Autodesk Fusion 360 part; units mm, degrees
(part 2 of 3)
sketch "Sketch3" plane through (0, -4, 0) normal (0, -1, 0) x (1, 0, 0)
  line L0 (-7.05, 59.625) -> (-3.6735, 85.6389)
  line L1 (-3.6735, 85.6389) -> (56.3105, 101.7115)
  line L2 (56.3105, 101.7115) -> (67.4527, 60.1284)
  line L3 (67.4527, 60.1284) -> (69.15, 48.195)
  line L4 (69.15, 48.195) -> (69.15, -71.055)
  line L5 (69.15, -71.055) -> (31.05, -71.055)
  line L6 (31.05, -71.055) -> (31.05, -76.77)
  line L7 (31.05, -76.77) -> (7.05, -76.77)
  line L8 (7.05, -76.77) -> (7.05, -69.15)
  line L9 (7.05, -69.15) -> (-12, -69.15)
  line L10 (-12, -69.15) -> (-12, -59.625)
  line L11 (-12, -59.625) -> (-69.15, -59.625)
  line L12 (-69.15, -59.625) -> (-69.15, 59.625)
  line L13 (-69.15, 59.625) -> (-7.05, 59.625)
  line L14 (-12.7285, 93.5653) -> (-15.8359, 69.625)
  line L15 (-15.8359, 69.625) -> (-79.15, 69.625)
  line L16 (-79.15, 69.625) -> (-79.15, -69.625)
  line L17 (-79.15, -69.625) -> (-22, -69.625)
  line L18 (-22, -69.625) -> (-22, -79.15)
  line L19 (-22, -79.15) -> (-2.95, -79.15)
  line L20 (-2.95, -79.15) -> (-2.95, -86.77)
  line L21 (-2.95, -86.77) -> (41.05, -86.77)
  line L22 (41.05, -86.77) -> (41.05, -81.055)
  line L23 (41.05, -81.055) -> (79.15, -81.055)
  line L24 (79.15, -81.055) -> (79.15, 48.9026)
  line L25 (79.15, 48.9026) -> (77.2681, 62.1339)
  line L26 (77.2681, 62.1339) -> (63.3816, 113.959)
  line L27 (63.3816, 113.959) -> (-12.7285, 93.5653)
  line L28 (69.15, -71.055) -> (59.15, -71.055)
  line L29 (59.15, -71.055) -> (59.15, -81.055)
  line L30 (69.15, -71.055) -> (69.15, -61.055)
  line L31 (69.15, -61.055) -> (79.15, -61.055)
  line L32 (-69.15, -59.625) -> (-59.15, -59.625)
  line L33 (-59.15, -59.625) -> (-59.15, -69.625)
  line L34 (-69.15, -59.625) -> (-69.15, -49.625)
  line L35 (-69.15, -49.625) -> (-79.15, -49.625)
  line L36 (-69.15, 59.625) -> (-59.15, 59.625)
  line L37 (-59.15, 59.625) -> (-59.15, 69.625)
  line L38 (-69.15, 59.625) -> (-69.15, 49.625)
  line L39 (-69.15, 49.625) -> (-79.15, 49.625)
  line L40 (56.3105, 101.7115) -> (58.8987, 92.0523)
  line L41 (58.8987, 92.0523) -> (68.558, 94.6405)
  line L42 (56.3105, 101.7115) -> (46.6513, 99.1233)
  line L43 (46.6513, 99.1233) -> (44.0631, 108.7826)
  line L44 (56.3105, 101.7115) -> (63.3816, 113.959) construction
  circle A0 centre (63.3816, 113.959) radius 8.75 construction
  circle A1 centre (59.0066, 106.3813) radius 1.75
  line L45 (-69.15, 59.625) -> (-79.15, 69.625) construction
  circle A2 centre (-79.15, 69.625) radius 8.75 construction
  line L46 (-69.15, -59.625) -> (-79.15, -69.625) construction
  circle A3 centre (-79.15, -69.625) radius 8.75 construction
  line L47 (69.15, -71.055) -> (79.15, -81.055) construction
  circle A4 centre (79.15, -81.055) radius 8.75 construction
  circle A5 centre (-72.9628, 63.4378) radius 1.75
  circle A6 centre (-72.9628, -63.4378) radius 1.75
  circle A7 centre (72.9628, -74.8678) radius 1.75
  line L48 (-3.6735, 85.6389) -> (-12.7285, 93.5653) construction
  line L49 (19.05, -86.77) -> (19.05, -74.6491) construction
  line L50 (-12, -59.625) -> (-59.15, -59.625) construction
  line L51 (-35.575, -59.625) -> (-35.575, -69.625) construction
  line L52 (69.15, 48.195) -> (79.15, 48.195) construction
  line L53 (74.15, -61.055) -> (74.15, 48.195) construction
  line L54 (-74.15, -49.625) -> (-74.15, 49.625) construction
  line L55 (-74.15, -49.625) -> (-116.3664, 10.6447) construction
  circle A8 centre (-116.3664, 10.6447) radius 73.5844 construction
  circle A9 centre (-158.5827, 70.9145) radius 73.5844 construction
  line L56 (-116.3664, 10.6447) -> (-188.0343, 112.9607) construction
  line L57 (-200.7991, 131.1842) -> (-74.15, 49.625) construction
  circle A10 centre (-200.7991, 131.1842) radius 73.5844 construction
  line L58 (-158.5827, 70.9145) -> (-138.933, 91.3438) construction
  circle A11 centre (-116.3664, 10.6447) radius 28.3455 construction
  line L59 (-116.3664, 10.6447) -> (-144.4165, 6.563) construction
  line L60 (-158.5827, 70.9145) -> (-96.7167, 31.0741) construction
  line L61 (-96.7167, 31.0741) -> (-29.6505, -12.115) construction
  circle A12 centre (-74.15, -49.625) radius 28.3455 construction
  line L62 (-74.15, -49.625) -> (-99.7632, -37.4829) construction
  line L63 (-116.3664, 10.6447) -> (-54.5003, -29.1956) construction
  circle A13 centre (-74.15, 16.5417) radius 1.25
  circle A14 centre (-74.15, -16.5417) radius 1.25
  circle A15 centre (19.05, -80.7095) radius 1.25
  circle A16 centre (-35.575, -64.625) radius 1.25
  line L64 (-7.05, 59.625) -> (-15.8359, 69.625) construction
  line L65 (-59.15, 64.625) -> (-11.443, 64.625) construction
  circle A17 centre (-35.2965, 64.625) radius 1.25
  line L66 (-5.3617, 72.6319) -> (-14.2822, 81.5952) construction
  line L67 (26.3185, 93.6752) -> (23.7303, 103.3345) construction
  line L68 (25.0244, 98.5048) -> (-9.822, 77.1136) construction
  line L69 (7.6012, 87.8092) -> (-12.7285, 93.5653) construction
  line L70 (-2.5637, 90.6873) -> (-8.201, 89.6021) construction
  line L71 (-2.5637, 90.6873) -> (-6.6059, 88.2058) construction
  line L72 (-6.6059, 88.2058) -> (-8.201, 89.6021) construction
  circle A18 centre (-7.4035, 88.904) radius 1.25
  line L73 (74.15, -61.055) -> (120.3943, 61.6463) construction
  circle A19 centre (74.15, -61.055) radius 30 construction
  circle A20 centre (84.7301, -32.9826) radius 30 construction
  circle A21 centre (95.3102, -4.9101) radius 30 construction
  circle A22 centre (105.8902, 23.1623) radius 30 construction
  line L74 (105.8902, 23.1623) -> (74.15, 48.195) construction
  line L75 (95.3102, -4.9101) -> (82.3346, 41.74) construction
  circle A23 centre (84.7301, -32.9826) radius 48.4211 construction
  circle A24 centre (74.15, -61.055) radius 48.4211 construction
  line L76 (74.15, -61.055) -> (120.8632, -73.8016) construction
  line L77 (84.7301, -32.9826) -> (131.4433, -45.7292) construction
  line L78 (95.3102, -4.9101) -> (71.7545, 13.6676) construction
  line L79 (84.7301, -32.9826) -> (61.1744, -14.4048) construction
  circle A25 centre (74.15, 11.7783) radius 1.25
  circle A26 centre (74.15, -24.6383) radius 1.25
  line L80 (67.4527, 60.1284) -> (77.1119, 62.7166) construction
  line L81 (72.2823, 61.4225) -> (63.7283, 93.3464) construction
  line L82 (72.2823, 61.4225) -> (80.0066, 107.5296) construction
  circle A27 centre (72.2823, 61.4225) radius 10 construction
  circle A28 centre (73.9346, 71.2851) radius 10 construction
  circle A29 centre (75.5869, 81.1476) radius 10 construction
  circle A30 centre (77.2391, 91.0102) radius 10 construction
  line L83 (77.2391, 91.0102) -> (63.7283, 93.3464) construction
  line L84 (75.5869, 81.1476) -> (67.3854, 92.714) construction
  circle A31 centre (72.2823, 61.4225) radius 14.1791 construction
  line L85 (72.2823, 61.4225) -> (86.4251, 60.4088) construction
  line L86 (64.0808, 72.9889) -> (73.9346, 71.2851) construction
  circle A32 centre (69.431, 72.0638) radius 1.25
  point P0 (-74.15, -16.5417)
  point P1 (-74.15, 16.5417)
  dimension "d195" = 10
  dimension "d196" = 10
  dimension "d197" = 10
  dimension "d198" = 10
  dimension "d199" = 10
  dimension "d200" = 10
  dimension "d201" = 10
  dimension "d202" = 10
  dimension "d203" = 17.5
  dimension "d204" = 3.5
  dimension "d205" = 17.5
  dimension "d206" = 17.5
  dimension "d207" = 17.5
  dimension "d208" = 3.5
  dimension "d209" = 3.5
  dimension "d210" = 3.5
  dimension "d216" = 2.5
  dimension "d217" = 2.5
  dimension "d218" = 2.5
  dimension "d219" = 2.5
  dimension "d224" = 2.5
  dimension "d250" = 2.5
  dimension "d251" = 60
  dimension "d252" = 60
  dimension "d253" = 60
  dimension "d254" = 2.5
  dimension "d255" = 2.5
  dimension "d261" = 20
  dimension "d262" = 2.5
  constraint coincident L4.end L5.start
  constraint perpendicular L4 L28
  constraint coincident L23 L29.end
  constraint perpendicular L23 L29
  constraint perpendicular L5 L30
  constraint coincident L24 L31.end
  constraint perpendicular L24 L31
  constraint coincident L11.end L12.start
  constraint perpendicular L12 L32
  constraint coincident L17 L33.end
  constraint perpendicular L17 L33
  constraint perpendicular L11 L34
  constraint coincident L16 L35.end
  constraint perpendicular L16 L35
  constraint coincident L12.end L13.start
  constraint perpendicular L12 L36
  constraint coincident L15 L37.end
  constraint perpendicular L15 L37
  constraint perpendicular L13 L38
  constraint coincident L16 L39.end
  constraint perpendicular L16 L39
  constraint coincident L1.end L2.start
  constraint perpendicular L1 L40
  constraint coincident L26 L41.end
  constraint perpendicular L26 L41
  constraint perpendicular L2 L42
  constraint coincident L27 L43.end
  constraint perpendicular L27 L43
  constraint coincident L26.end L27.start
  constraint coincident A0 A1.centre
  constraint coincident L44 A1.centre
  constraint coincident L15.end L16.start
  constraint coincident L16.end L17.start
  constraint coincident L23.end L24.start
  constraint coincident A2 A5.centre
  constraint coincident L45 A5.centre
  constraint coincident A3 A6.centre
  constraint coincident L46 A6.centre
  constraint coincident A4 A7.centre
  constraint coincident L47 A7.centre
  constraint coincident L0.end L1.start
  constraint coincident L14.start L27.end
  constraint midpoint L21 L49.start
  constraint perpendicular L21 L49
  constraint coincident L10.end L11.start
  constraint midpoint L50 L51.start
  constraint coincident L17 L51.end
  constraint perpendicular L17 L51
  constraint coincident L3.end L4.start
  constraint coincident L24 L52.end
  constraint perpendicular L24 L52
  constraint midpoint L31 L53.start
  constraint midpoint L52 L53.end
  constraint midpoint L35 L54.start
  constraint midpoint L39 L54.end
  constraint coincident L55.end A8.centre
  constraint coincident L54.start A8
  constraint coincident A8 A9.centre
  constraint coincident L55.end A9
  constraint coincident A9 L57.start
  constraint coincident L56 L57.start
  constraint coincident L57.start A10.centre
  constraint coincident A9.centre A10
  constraint coincident A9.centre L58.start
  constraint coincident A10 L58.end
  constraint coincident L57 L58.end
  constraint coincident A11 L59.end
  constraint collinear L55 L56
  constraint collinear A9.centre L56.end L55.end
  constraint collinear L54.start L57.start L55.end
  constraint concentric A8 A11
  constraint equal L58 L59
  constraint coincident A9 L60.end
  constraint coincident A11 L60.end
  constraint collinear L60 L61
  constraint coincident L54.start L55.start
  constraint coincident A12 L62.end
  constraint equal L58 L62
  constraint coincident A12 L63.end
  constraint coincident A8 L63.end
  constraint coincident L63 P0
  constraint coincident L54 P0
  constraint coincident L61 P1
  constraint coincident L54 P1
  constraint coincident P1 A13.centre
  constraint coincident P0 A14.centre
  constraint midpoint L49 A15.centre
  constraint midpoint L51 A16.centre
  constraint coincident L0.start L13.end
  constraint coincident L14.end L15.start
  constraint midpoint L37 L65.start
  constraint midpoint L64 L65.end
  constraint midpoint L65 A17.centre
  constraint midpoint L0 L66.start
  constraint midpoint L14 L66.end
  constraint midpoint L1 L67.start
  constraint coincident L27 L67.end
  constraint perpendicular L27 L67
  constraint midpoint L67 L68.start
  constraint midpoint L66 L68.end
  constraint midpoint L68 L69.start
  constraint midpoint L69 L70.start
  constraint midpoint L48 L70.end
  constraint coincident L48 L71.end
  constraint parallel L68 L71
  constraint midpoint L72 A18.centre
  constraint coincident L53.start L73.start
  constraint coincident A19 A20.centre
  constraint coincident L73 A20.centre
  constraint coincident A20 A21.centre
  constraint coincident L73 A21.centre
  constraint coincident A21 A22.centre
  constraint coincident L73 A22.centre
  constraint coincident A21.centre A22
  constraint coincident A22.centre L74.start
  constraint coincident A21.centre L75.start
  constraint coincident A22 L75.end
  constraint coincident L74 L75.end
  constraint concentric A20 A23
  constraint coincident A24 L76.end
  constraint coincident A20.centre A23.centre
  constraint coincident A23 L77.end
  constraint parallel L76 L77
  constraint equal L75 L77
  constraint equal L75 L76
  constraint coincident A23 L78.end
  constraint coincident A21 L78.end
  constraint coincident A20 L79.end
  constraint coincident A24 L79.end
  constraint coincident L78 A25.centre
  constraint coincident L53 A25.centre
  constraint coincident L79 A26.centre
  constraint coincident L53 A26.centre
  constraint coincident L2.end L3.start
  constraint coincident L26 L80.end
  constraint perpendicular L26 L80
  constraint midpoint L80 L81.start
  constraint midpoint L41 L81.end
  constraint coincident L81.start L82.start
  constraint coincident A27 A28.centre
  constraint coincident L82 A28.centre
  constraint coincident L81.start A28
  constraint coincident A28 A29.centre
  constraint coincident L82 A29.centre
  constraint coincident A28.centre A29
  constraint coincident L82 A30.centre
  constraint coincident A29 A30.centre
  constraint coincident A29.centre A30
  constraint coincident A30.centre L83.start
  constraint coincident A29.centre L84.start
  constraint coincident A30 L84.end
  constraint coincident L83 L84.end
  constraint coincident A31 L85.end
  constraint equal L84 L85
  constraint coincident A28 L86.start
  constraint coincident A31 L86.start
  constraint coincident A28.centre L86.end
  constraint coincident L81 A32.centre
  constraint coincident L86 A32.centre
  measures "d195" distance of L4.end L28.end
  measures "d196" distance of L4.end L30.end
  measures "d197" distance of L11.end L32.end
  measures "d198" distance of L11.end L34.end
  measures "d199" distance of L12.end L36.end
  measures "d200" distance of L12.end L38.end
  measures "d201" distance of L1.end L40.end
  measures "d202" distance of L1.end L42.end
  measures "d203" diameter of A0
  measures "d204" diameter of A1
  measures "d205" diameter of A2
  measures "d206" diameter of A3
  measures "d207" diameter of A4
  measures "d208" diameter of A5
  measures "d209" diameter of A6
  measures "d210" diameter of A7
  measures "d216" diameter of A13
  measures "d217" diameter of A14
  measures "d218" diameter of A15
  measures "d219" diameter of A16
  measures "d224" diameter of A17
  measures "d250" diameter of A18
  measures "d251" diameter of A19
  measures "d252" diameter of A20
  measures "d253" diameter of A21
  measures "d254" diameter of A25
  measures "d255" diameter of A26
  measures "d261" diameter of A27
  measures "d262" diameter of A32
extrude "Extrude5" add sketch "Sketch3" along normal blind 3.2 contours L12 L13 L15 L16 L36 L37 L38 L39 | L1 L2 L26 L27 L40 L41 L42 L43 | L11 L12 L16 L17 L32 L33 L34 L35 | L4 L5 L23 L24 L28 L29 L30 L31
extrude "Extrude4" add sketch "Sketch3" along normal blind 0.7 contours A1 | A5 | A6 | A7
extrude "Extrude6" add sketch "Sketch3" along normal blind 5 contours A13 | A14 | A15 | A16 | A17 | A18 | A25 | A26 | A32
fillet "Fillet2" radius 1.25 9 edges at (-36.4619, -9, 64.173) (17.8846, -9, -81.1616) (-36.7404, -9, -65.077) (-75.3154, -9, -16.9937) (-75.3154, -9, 16.0896) (-8.5689, -9, 88.4519) (72.9846, -9, 11.3263) (72.9846, -9, -25.0904) (68.2656, -9, 71.6118)
extrude "Extrude7" add sketch "Sketch1" along normal blind 2.5
sketch "Sketch4" plane through (0, 0, 0) normal (0, 1, 0) x (-1, 0, 0)
  line L0 (3.6735, 85.6389) -> (-56.3105, 101.7115)
  line L1 (-56.3105, 101.7115) -> (-67.4527, 60.1284)
  line L2 (-67.4527, 60.1284) -> (-69.15, 48.195)
  line L3 (-69.15, 48.195) -> (-69.15, -71.055)
  line L4 (-69.15, -71.055) -> (-31.05, -71.055)
  line L5 (-31.05, -71.055) -> (-31.05, -76.77)
  line L6 (-31.05, -76.77) -> (-7.05, -76.77)
  line L7 (-7.05, -76.77) -> (-7.05, -69.15)
  line L8 (-7.05, -69.15) -> (12, -69.15)
  line L9 (12, -69.15) -> (12, -59.625)
  line L10 (12, -59.625) -> (69.15, -59.625)
  line L11 (69.15, -59.625) -> (69.15, 59.625)
  line L12 (69.15, 59.625) -> (7.05, 59.625)
  line L13 (7.05, 59.625) -> (3.6735, 85.6389)
  line L14 (-21.0175, 72.1887) -> (-17.2125, 86.4394)
  arc A0 (-15.9884, 87.1476) -> (-17.2125, 86.4394) centre (-16.2463, 86.1815) ccw
  line L15 (-15.9884, 87.1476) -> (-1.7376, 83.3426)
  arc A1 (-1.0294, 82.1185) -> (-1.7376, 83.3426) centre (-1.9956, 82.3765) ccw
  line L16 (-1.0294, 82.1185) -> (-4.8344, 67.8677)
  arc A2 (-6.0585, 67.1595) -> (-4.8344, 67.8677) centre (-5.8006, 68.1257) ccw
  line L17 (-6.0585, 67.1595) -> (-20.3093, 70.9646)
  arc A3 (-21.0175, 72.1887) -> (-20.3093, 70.9646) centre (-20.0513, 71.9307) ccw
  line L18 (-44.3489, 58.7183) -> (-40.5439, 72.9691)
  arc A4 (-39.3198, 73.6772) -> (-40.5439, 72.9691) centre (-39.5777, 72.7111) ccw
  line L19 (-39.3198, 73.6772) -> (-25.069, 69.8722)
  arc A5 (-24.3608, 68.6481) -> (-25.069, 69.8722) centre (-25.327, 68.9061) ccw
  line L20 (-24.3608, 68.6481) -> (-28.1658, 54.3974)
  arc A6 (-29.3899, 53.6892) -> (-28.1658, 54.3974) centre (-29.132, 54.6553) ccw
  line L21 (-29.3899, 53.6892) -> (-43.6407, 57.4942)
  arc A7 (-44.3489, 58.7183) -> (-43.6407, 57.4942) centre (-43.3827, 58.4603) ccw
  line L22 (-46.475, 9.77) -> (-46.475, 24.52)
  arc A8 (-45.475, 25.52) -> (-46.475, 24.52) centre (-45.475, 24.52) ccw
  line L23 (-45.475, 25.52) -> (-30.725, 25.52)
  arc A9 (-29.725, 24.52) -> (-30.725, 25.52) centre (-30.725, 24.52) ccw
  line L24 (-29.725, 24.52) -> (-29.725, 9.77)
  arc A10 (-30.725, 8.77) -> (-29.725, 9.77) centre (-30.725, 9.77) ccw
  line L25 (-30.725, 8.77) -> (-45.475, 8.77)
  arc A11 (-46.475, 9.77) -> (-45.475, 8.77) centre (-45.475, 9.77) ccw
  line L26 (-46.475, -9.28) -> (-46.475, 5.47)
  arc A12 (-45.475, 6.47) -> (-46.475, 5.47) centre (-45.475, 5.47) ccw
  line L27 (-45.475, 6.47) -> (-30.725, 6.47)
  arc A13 (-29.725, 5.47) -> (-30.725, 6.47) centre (-30.725, 5.47) ccw
  line L28 (-29.725, 5.47) -> (-29.725, -9.28)
  arc A14 (-30.725, -10.28) -> (-29.725, -9.28) centre (-30.725, -9.28) ccw
  line L29 (-30.725, -10.28) -> (-45.475, -10.28)
  arc A15 (-46.475, -9.28) -> (-45.475, -10.28) centre (-45.475, -9.28) ccw
  line L30 (-8.375, -26.425) -> (-8.375, -11.675)
  arc A16 (-7.375, -10.675) -> (-8.375, -11.675) centre (-7.375, -11.675) ccw
  line L31 (-7.375, -10.675) -> (7.375, -10.675)
  arc A17 (8.375, -11.675) -> (7.375, -10.675) centre (7.375, -11.675) ccw
  line L32 (8.375, -11.675) -> (8.375, -26.425)
  arc A18 (7.375, -27.425) -> (8.375, -26.425) centre (7.375, -26.425) ccw
  line L33 (7.375, -27.425) -> (-7.375, -27.425)
  arc A19 (-8.375, -26.425) -> (-7.375, -27.425) centre (-7.375, -26.425) ccw
  line L34 (-8.375, 30.725) -> (-8.375, 45.475)
  arc A20 (-7.375, 46.475) -> (-8.375, 45.475) centre (-7.375, 45.475) ccw
  line L35 (-7.375, 46.475) -> (7.375, 46.475)
  arc A21 (8.375, 45.475) -> (7.375, 46.475) centre (7.375, 45.475) ccw
  line L36 (8.375, 45.475) -> (8.375, 30.725)
  arc A22 (7.375, 29.725) -> (8.375, 30.725) centre (7.375, 30.725) ccw
  line L37 (7.375, 29.725) -> (-7.375, 29.725)
  arc A23 (-8.375, 30.725) -> (-7.375, 29.725) centre (-7.375, 30.725) ccw
  line L38 (11.675, 17.9) -> (26.425, 17.9)
  arc A24 (27.425, 16.9) -> (26.425, 17.9) centre (26.425, 16.9) ccw
  line L39 (27.425, 16.9) -> (27.425, 2.15)
  arc A25 (26.425, 1.15) -> (27.425, 2.15) centre (26.425, 2.15) ccw
  line L40 (26.425, 1.15) -> (11.675, 1.15)
  arc A26 (10.675, 2.15) -> (11.675, 1.15) centre (11.675, 2.15) ccw
  line L41 (10.675, 2.15) -> (10.675, 16.9)
  arc A27 (11.675, 17.9) -> (10.675, 16.9) centre (11.675, 16.9) ccw
  line L42 (30.725, -1.15) -> (64.525, -1.15)
  arc A28 (65.525, -2.15) -> (64.525, -1.15) centre (64.525, -2.15) ccw
  line L43 (65.525, -2.15) -> (65.525, -16.9)
  arc A29 (64.525, -17.9) -> (65.525, -16.9) centre (64.525, -16.9) ccw
  line L44 (64.525, -17.9) -> (30.725, -17.9)
  arc A30 (29.725, -16.9) -> (30.725, -17.9) centre (30.725, -16.9) ccw
  line L45 (29.725, -16.9) -> (29.725, -2.15)
  arc A31 (30.725, -1.15) -> (29.725, -2.15) centre (30.725, -2.15) ccw
  line L46 (-8.375, -45.475) -> (-8.375, -30.725)
  arc A32 (-7.375, -29.725) -> (-8.375, -30.725) centre (-7.375, -30.725) ccw
  line L47 (-7.375, -29.725) -> (7.375, -29.725)
  arc A33 (8.375, -30.725) -> (7.375, -29.725) centre (7.375, -30.725) ccw
  line L48 (8.375, -30.725) -> (8.375, -45.475)
  arc A34 (7.375, -46.475) -> (8.375, -45.475) centre (7.375, -45.475) ccw
  line L49 (7.375, -46.475) -> (-7.375, -46.475)
  arc A35 (-8.375, -45.475) -> (-7.375, -46.475) centre (-7.375, -45.475) ccw
  line L50 (-65.525, -66.43) -> (-65.525, -51.68)
  arc A36 (-64.525, -50.68) -> (-65.525, -51.68) centre (-64.525, -51.68) ccw
  line L51 (-64.525, -50.68) -> (-49.775, -50.68)
  arc A37 (-48.775, -51.68) -> (-49.775, -50.68) centre (-49.775, -51.68) ccw
  line L52 (-48.775, -51.68) -> (-48.775, -66.43)
  arc A38 (-49.775, -67.43) -> (-48.775, -66.43) centre (-49.775, -66.43) ccw
  line L53 (-49.775, -67.43) -> (-64.525, -67.43)
  arc A39 (-65.525, -66.43) -> (-64.525, -67.43) centre (-64.525, -66.43) ccw
  line L54 (11.675, -39.25) -> (26.425, -39.25)
  arc A40 (27.425, -40.25) -> (26.425, -39.25) centre (26.425, -40.25) ccw
  line L55 (27.425, -40.25) -> (27.425, -55)
  arc A41 (26.425, -56) -> (27.425, -55) centre (26.425, -55) ccw
  line L56 (26.425, -56) -> (11.675, -56)
  arc A42 (10.675, -55) -> (11.675, -56) centre (11.675, -55) ccw
  line L57 (10.675, -55) -> (10.675, -40.25)
  arc A43 (11.675, -39.25) -> (10.675, -40.25) centre (11.675, -40.25) ccw
  line L58 (-7.375, -48.775) -> (7.375, -48.775)
  arc A44 (8.375, -49.775) -> (7.375, -48.775) centre (7.375, -49.775) ccw
  line L59 (8.375, -49.775) -> (8.375, -64.525)
  arc A45 (7.375, -65.525) -> (8.375, -64.525) centre (7.375, -64.525) ccw
  line L60 (7.375, -65.525) -> (-7.375, -65.525)
  arc A46 (-8.375, -64.525) -> (-7.375, -65.525) centre (-7.375, -64.525) ccw
  line L61 (-8.375, -64.525) -> (-8.375, -49.775)
  arc A47 (-7.375, -48.775) -> (-8.375, -49.775) centre (-7.375, -49.775) ccw
  line L62 (-65.525, -47.38) -> (-65.525, -32.63)
  arc A48 (-64.525, -31.63) -> (-65.525, -32.63) centre (-64.525, -32.63) ccw
  line L63 (-64.525, -31.63) -> (-49.775, -31.63)
  arc A49 (-48.775, -32.63) -> (-49.775, -31.63) centre (-49.775, -32.63) ccw
  line L64 (-48.775, -32.63) -> (-48.775, -47.38)
  arc A50 (-49.775, -48.38) -> (-48.775, -47.38) centre (-49.775, -47.38) ccw
  line L65 (-49.775, -48.38) -> (-64.525, -48.38)
  arc A51 (-65.525, -47.38) -> (-64.525, -48.38) centre (-64.525, -47.38) ccw
  line L66 (11.675, -20.2) -> (26.425, -20.2)
  arc A52 (27.425, -21.2) -> (26.425, -20.2) centre (26.425, -21.2) ccw
  line L67 (27.425, -21.2) -> (27.425, -35.95)
  arc A53 (26.425, -36.95) -> (27.425, -35.95) centre (26.425, -35.95) ccw
  line L68 (26.425, -36.95) -> (11.675, -36.95)
  arc A54 (10.675, -35.95) -> (11.675, -36.95) centre (11.675, -35.95) ccw
  line L69 (10.675, -35.95) -> (10.675, -21.2)
  arc A55 (11.675, -20.2) -> (10.675, -21.2) centre (11.675, -21.2) ccw
  line L70 (30.725, 17.9) -> (64.525, 17.9)
  arc A56 (65.525, 16.9) -> (64.525, 17.9) centre (64.525, 16.9) ccw
  line L71 (65.525, 16.9) -> (65.525, 2.15)
  arc A57 (64.525, 1.15) -> (65.525, 2.15) centre (64.525, 2.15) ccw
  line L72 (64.525, 1.15) -> (30.725, 1.15)
  arc A58 (29.725, 2.15) -> (30.725, 1.15) centre (30.725, 2.15) ccw
  line L73 (29.725, 2.15) -> (29.725, 16.9)
  arc A59 (30.725, 17.9) -> (29.725, 16.9) centre (30.725, 16.9) ccw
  line L74 (11.675, -1.15) -> (26.425, -1.15)
  arc A60 (27.425, -2.15) -> (26.425, -1.15) centre (26.425, -2.15) ccw
  line L75 (27.425, -2.15) -> (27.425, -16.9)
  arc A61 (26.425, -17.9) -> (27.425, -16.9) centre (26.425, -16.9) ccw
  line L76 (26.425, -17.9) -> (11.675, -17.9)
  arc A62 (10.675, -16.9) -> (11.675, -17.9) centre (11.675, -16.9) ccw
  line L77 (10.675, -16.9) -> (10.675, -2.15)
  arc A63 (11.675, -1.15) -> (10.675, -2.15) centre (11.675, -2.15) ccw
  line L78 (10.675, 40.25) -> (10.675, 55)
  arc A64 (11.675, 56) -> (10.675, 55) centre (11.675, 55) ccw
  line L79 (11.675, 56) -> (26.425, 56)
  arc A65 (27.425, 55) -> (26.425, 56) centre (26.425, 55) ccw
  line L80 (27.425, 55) -> (27.425, 40.25)
  arc A66 (26.425, 39.25) -> (27.425, 40.25) centre (26.425, 40.25) ccw
  line L81 (26.425, 39.25) -> (11.675, 39.25)
  arc A67 (10.675, 40.25) -> (11.675, 39.25) centre (11.675, 40.25) ccw
  line L82 (-27.425, -34.045) -> (-27.425, -19.295)
  arc A68 (-26.425, -18.295) -> (-27.425, -19.295) centre (-26.425, -19.295) ccw
  line L83 (-26.425, -18.295) -> (-11.675, -18.295)
  arc A69 (-10.675, -19.295) -> (-11.675, -18.295) centre (-11.675, -19.295) ccw
  line L84 (-10.675, -19.295) -> (-10.675, -34.045)
  arc A70 (-11.675, -35.045) -> (-10.675, -34.045) centre (-11.675, -34.045) ccw
  line L85 (-11.675, -35.045) -> (-26.425, -35.045)
  arc A71 (-27.425, -34.045) -> (-26.425, -35.045) centre (-26.425, -34.045) ccw
  line L86 (-65.525, -28.33) -> (-65.525, -13.58)
  arc A72 (-64.525, -12.58) -> (-65.525, -13.58) centre (-64.525, -13.58) ccw
  line L87 (-64.525, -12.58) -> (-49.775, -12.58)
  arc A73 (-48.775, -13.58) -> (-49.775, -12.58) centre (-49.775, -13.58) ccw
  line L88 (-48.775, -13.58) -> (-48.775, -28.33)
  arc A74 (-49.775, -29.33) -> (-48.775, -28.33) centre (-49.775, -28.33) ccw
  line L89 (-49.775, -29.33) -> (-64.525, -29.33)
  arc A75 (-65.525, -28.33) -> (-64.525, -29.33) centre (-64.525, -28.33) ccw
  line L90 (-27.425, 4.055) -> (-27.425, 18.805)
  arc A76 (-26.425, 19.805) -> (-27.425, 18.805) centre (-26.425, 18.805) ccw
  line L91 (-26.425, 19.805) -> (-11.675, 19.805)
  arc A77 (-10.675, 18.805) -> (-11.675, 19.805) centre (-11.675, 18.805) ccw
  line L92 (-10.675, 18.805) -> (-10.675, 4.055)
  arc A78 (-11.675, 3.055) -> (-10.675, 4.055) centre (-11.675, 4.055) ccw
  line L93 (-11.675, 3.055) -> (-26.425, 3.055)
  arc A79 (-27.425, 4.055) -> (-26.425, 3.055) centre (-26.425, 4.055) ccw
  line L94 (-62.7498, 63.6488) -> (-58.9448, 77.8996)
  arc A80 (-57.7207, 78.6078) -> (-58.9448, 77.8996) centre (-57.9786, 77.6416) ccw
  line L95 (-57.7207, 78.6078) -> (-43.4699, 74.8027)
  arc A81 (-42.7617, 73.5786) -> (-43.4699, 74.8027) centre (-43.7278, 73.8366) ccw
  line L96 (-42.7617, 73.5786) -> (-46.5667, 59.3279)
  arc A82 (-47.7908, 58.6197) -> (-46.5667, 59.3279) centre (-47.5329, 59.5858) ccw
  line L97 (-47.7908, 58.6197) -> (-62.0416, 62.4247)
  arc A83 (-62.7498, 63.6488) -> (-62.0416, 62.4247) centre (-61.7836, 63.3908) ccw
  line L98 (-39.4184, 77.1192) -> (-35.6134, 91.3699)
  arc A84 (-34.3893, 92.0781) -> (-35.6134, 91.3699) centre (-34.6472, 91.112) ccw
  line L99 (-34.3893, 92.0781) -> (-20.1385, 88.2731)
  arc A85 (-19.4303, 87.049) -> (-20.1385, 88.2731) centre (-20.3965, 87.307) ccw
  line L100 (-19.4303, 87.049) -> (-23.2353, 72.7982)
  arc A86 (-24.4594, 72.0901) -> (-23.2353, 72.7982) centre (-24.2015, 73.0562) ccw
  line L101 (-24.4594, 72.0901) -> (-38.7102, 75.8951)
  arc A87 (-39.4184, 77.1192) -> (-38.7102, 75.8951) centre (-38.4522, 76.8612) ccw
  line L102 (-20.9189, 68.7467) -> (-6.6681, 64.9417)
  arc A88 (-5.9599, 63.7176) -> (-6.6681, 64.9417) centre (-6.9261, 63.9756) ccw
  line L103 (-5.9599, 63.7176) -> (-9.7649, 49.4669)
  arc A89 (-10.989, 48.7587) -> (-9.7649, 49.4669) centre (-10.7311, 49.7248) ccw
  line L104 (-10.989, 48.7587) -> (-25.2398, 52.5637)
  arc A90 (-25.948, 53.7878) -> (-25.2398, 52.5637) centre (-24.9818, 53.5298) ccw
  line L105 (-25.948, 53.7878) -> (-22.143, 68.0386)
  arc A91 (-20.9189, 68.7467) -> (-22.143, 68.0386) centre (-21.1768, 67.7806) ccw
  line L106 (-65.525, 9.77) -> (-65.525, 24.52)
  arc A92 (-64.525, 25.52) -> (-65.525, 24.52) centre (-64.525, 24.52) ccw
  line L107 (-64.525, 25.52) -> (-49.775, 25.52)
  arc A93 (-48.775, 24.52) -> (-49.775, 25.52) centre (-49.775, 24.52) ccw
  line L108 (-48.775, 24.52) -> (-48.775, 9.77)
  arc A94 (-49.775, 8.77) -> (-48.775, 9.77) centre (-49.775, 9.77) ccw
  line L109 (-49.775, 8.77) -> (-64.525, 8.77)
  arc A95 (-65.525, 9.77) -> (-64.525, 8.77) centre (-64.525, 9.77) ccw
  line L110 (-46.475, -28.33) -> (-46.475, -13.58)
  arc A96 (-45.475, -12.58) -> (-46.475, -13.58) centre (-45.475, -13.58) ccw
  line L111 (-45.475, -12.58) -> (-30.725, -12.58)
  arc A97 (-29.725, -13.58) -> (-30.725, -12.58) centre (-30.725, -13.58) ccw
  line L112 (-29.725, -13.58) -> (-29.725, -28.33)
  arc A98 (-30.725, -29.33) -> (-29.725, -28.33) centre (-30.725, -28.33) ccw
  line L113 (-30.725, -29.33) -> (-45.475, -29.33)
  arc A99 (-46.475, -28.33) -> (-45.475, -29.33) centre (-45.475, -28.33) ccw
  line L114 (-8.375, -7.375) -> (-8.375, 7.375)
  arc A100 (-7.375, 8.375) -> (-8.375, 7.375) centre (-7.375, 7.375) ccw
  line L115 (-7.375, 8.375) -> (7.375, 8.375)
  arc A101 (8.375, 7.375) -> (7.375, 8.375) centre (7.375, 7.375) ccw
  line L116 (8.375, 7.375) -> (8.375, -7.375)
  arc A102 (7.375, -8.375) -> (8.375, -7.375) centre (7.375, -7.375) ccw
  line L117 (7.375, -8.375) -> (-7.375, -8.375)
  arc A103 (-8.375, -7.375) -> (-7.375, -8.375) centre (-7.375, -7.375) ccw
  line L118 (29.725, 40.25) -> (29.725, 55)
  arc A104 (30.725, 56) -> (29.725, 55) centre (30.725, 55) ccw
  line L119 (30.725, 56) -> (45.475, 56)
  arc A105 (46.475, 55) -> (45.475, 56) centre (45.475, 55) ccw
  line L120 (46.475, 55) -> (46.475, 40.25)
  arc A106 (45.475, 39.25) -> (46.475, 40.25) centre (45.475, 40.25) ccw
  line L121 (45.475, 39.25) -> (30.725, 39.25)
  arc A107 (29.725, 40.25) -> (30.725, 39.25) centre (30.725, 40.25) ccw
  line L122 (11.675, 36.95) -> (26.425, 36.95)
  arc A108 (27.425, 35.95) -> (26.425, 36.95) centre (26.425, 35.95) ccw
  line L123 (27.425, 35.95) -> (27.425, 21.2)
  arc A109 (26.425, 20.2) -> (27.425, 21.2) centre (26.425, 21.2) ccw
  line L124 (26.425, 20.2) -> (11.675, 20.2)
  arc A110 (10.675, 21.2) -> (11.675, 20.2) centre (11.675, 21.2) ccw
  line L125 (10.675, 21.2) -> (10.675, 35.95)
  arc A111 (11.675, 36.95) -> (10.675, 35.95) centre (11.675, 35.95) ccw
  line L126 (48.775, -20.2) -> (64.525, -20.2)
  arc A112 (65.525, -21.2) -> (64.525, -20.2) centre (64.525, -21.2) ccw
  line L127 (65.525, -21.2) -> (65.525, -35.95)
  arc A113 (64.525, -36.95) -> (65.525, -35.95) centre (64.525, -35.95) ccw
  line L128 (64.525, -36.95) -> (49.775, -36.95)
  arc A114 (48.775, -35.95) -> (49.775, -36.95) centre (49.775, -35.95) ccw
  line L129 (48.775, -35.95) -> (48.775, -20.2)
  line L130 (-27.425, -53.095) -> (-27.425, -38.345)
  arc A115 (-26.425, -37.345) -> (-27.425, -38.345) centre (-26.425, -38.345) ccw
  line L131 (-26.425, -37.345) -> (-11.675, -37.345)
  arc A116 (-10.675, -38.345) -> (-11.675, -37.345) centre (-11.675, -38.345) ccw
  line L132 (-10.675, -38.345) -> (-10.675, -53.095)
  arc A117 (-11.675, -54.095) -> (-10.675, -53.095) centre (-11.675, -53.095) ccw
  line L133 (-11.675, -54.095) -> (-26.425, -54.095)
  arc A118 (-27.425, -53.095) -> (-26.425, -54.095) centre (-26.425, -53.095) ccw
  line L134 (-45.475, -50.68) -> (-30.725, -50.68)
  arc A119 (-29.725, -51.68) -> (-30.725, -50.68) centre (-30.725, -51.68) ccw
  line L135 (-29.725, -51.68) -> (-29.725, -66.43)
  arc A120 (-30.725, -67.43) -> (-29.725, -66.43) centre (-30.725, -66.43) ccw
  line L136 (-30.725, -67.43) -> (-45.475, -67.43)
  arc A121 (-46.475, -66.43) -> (-45.475, -67.43) centre (-45.475, -66.43) ccw
  line L137 (-46.475, -66.43) -> (-46.475, -51.68)
  arc A122 (-45.475, -50.68) -> (-46.475, -51.68) centre (-45.475, -51.68) ccw
  line L138 (29.725, -39.25) -> (64.525, -39.25)
  arc A123 (65.525, -40.25) -> (64.525, -39.25) centre (64.525, -40.25) ccw
  line L139 (65.525, -40.25) -> (65.525, -55)
  arc A124 (64.525, -56) -> (65.525, -55) centre (64.525, -55) ccw
  line L140 (64.525, -56) -> (30.725, -56)
  arc A125 (29.725, -55) -> (30.725, -56) centre (30.725, -55) ccw
  line L141 (29.725, -55) -> (29.725, -39.25)
  line L142 (-26.425, -56.395) -> (-11.675, -56.395)
  arc A126 (-10.675, -57.395) -> (-11.675, -56.395) centre (-11.675, -57.395) ccw
  line L143 (-10.675, -57.395) -> (-10.675, -72.145)
  arc A127 (-11.675, -73.145) -> (-10.675, -72.145) centre (-11.675, -72.145) ccw
  line L144 (-11.675, -73.145) -> (-26.425, -73.145)
  arc A128 (-27.425, -72.145) -> (-26.425, -73.145) centre (-26.425, -72.145) ccw
  line L145 (-27.425, -72.145) -> (-27.425, -57.395)
  arc A129 (-26.425, -56.395) -> (-27.425, -57.395) centre (-26.425, -57.395) ccw
  line L146 (-46.475, -47.38) -> (-46.475, -32.63)
  arc A130 (-45.475, -31.63) -> (-46.475, -32.63) centre (-45.475, -32.63) ccw
  line L147 (-45.475, -31.63) -> (-30.725, -31.63)
  arc A131 (-29.725, -32.63) -> (-30.725, -31.63) centre (-30.725, -32.63) ccw
  line L148 (-29.725, -32.63) -> (-29.725, -47.38)
  arc A132 (-30.725, -48.38) -> (-29.725, -47.38) centre (-30.725, -47.38) ccw
  line L149 (-30.725, -48.38) -> (-45.475, -48.38)
  arc A133 (-46.475, -47.38) -> (-45.475, -48.38) centre (-45.475, -47.38) ccw
  line L150 (29.725, -35.95) -> (29.725, -21.2)
  arc A134 (30.725, -20.2) -> (29.725, -21.2) centre (30.725, -21.2) ccw
  line L151 (30.725, -20.2) -> (45.475, -20.2)
  arc A135 (46.475, -21.2) -> (45.475, -20.2) centre (45.475, -21.2) ccw
  line L152 (46.475, -21.2) -> (46.475, -35.95)
  arc A136 (45.475, -36.95) -> (46.475, -35.95) centre (45.475, -35.95) ccw
  line L153 (45.475, -36.95) -> (30.725, -36.95)
  arc A137 (29.725, -35.95) -> (30.725, -36.95) centre (30.725, -35.95) ccw
  line L154 (30.725, 36.95) -> (64.525, 36.95)
  arc A138 (65.525, 35.95) -> (64.525, 36.95) centre (64.525, 35.95) ccw
  line L155 (65.525, 35.95) -> (65.525, 21.2)
  arc A139 (64.525, 20.2) -> (65.525, 21.2) centre (64.525, 21.2) ccw
  line L156 (64.525, 20.2) -> (30.725, 20.2)
  arc A140 (29.725, 21.2) -> (30.725, 20.2) centre (30.725, 21.2) ccw
  line L157 (29.725, 21.2) -> (29.725, 35.95)
  arc A141 (30.725, 36.95) -> (29.725, 35.95) centre (30.725, 35.95) ccw
  line L158 (49.775, 56) -> (64.525, 56)
  arc A142 (65.525, 55) -> (64.525, 56) centre (64.525, 55) ccw
  line L159 (65.525, 55) -> (65.525, 40.25)
  arc A143 (64.525, 39.25) -> (65.525, 40.25) centre (64.525, 40.25) ccw
  line L160 (64.525, 39.25) -> (49.775, 39.25)
  arc A144 (48.775, 40.25) -> (49.775, 39.25) centre (49.775, 40.25) ccw
  line L161 (48.775, 40.25) -> (48.775, 55)
  arc A145 (49.775, 56) -> (48.775, 55) centre (49.775, 55) ccw
  line L162 (-8.375, 11.675) -> (-8.375, 26.425)
  arc A146 (-7.375, 27.425) -> (-8.375, 26.425) centre (-7.375, 26.425) ccw
  line L163 (-7.375, 27.425) -> (7.375, 27.425)
  arc A147 (8.375, 26.425) -> (7.375, 27.425) centre (7.375, 26.425) ccw
  line L164 (8.375, 26.425) -> (8.375, 11.675)
  arc A148 (7.375, 10.675) -> (8.375, 11.675) centre (7.375, 11.675) ccw
  line L165 (7.375, 10.675) -> (-7.375, 10.675)
  arc A149 (-8.375, 11.675) -> (-7.375, 10.675) centre (-7.375, 11.675) ccw
  line L166 (-27.425, -14.995) -> (-27.425, -0.245)
  arc A150 (-26.425, 0.755) -> (-27.425, -0.245) centre (-26.425, -0.245) ccw
  line L167 (-26.425, 0.755) -> (-11.675, 0.755)
  arc A151 (-10.675, -0.245) -> (-11.675, 0.755) centre (-11.675, -0.245) ccw
  line L168 (-10.675, -0.245) -> (-10.675, -14.995)
  arc A152 (-11.675, -15.995) -> (-10.675, -14.995) centre (-11.675, -14.995) ccw
  line L169 (-11.675, -15.995) -> (-26.425, -15.995)
  arc A153 (-27.425, -14.995) -> (-26.425, -15.995) centre (-26.425, -14.995) ccw
  line L170 (-65.525, -9.28) -> (-65.525, 5.47)
  arc A154 (-64.525, 6.47) -> (-65.525, 5.47) centre (-64.525, 5.47) ccw
  line L171 (-64.525, 6.47) -> (-49.775, 6.47)
  arc A155 (-48.775, 5.47) -> (-49.775, 6.47) centre (-49.775, 5.47) ccw
  line L172 (-48.775, 5.47) -> (-48.775, -9.28)
  arc A156 (-49.775, -10.28) -> (-48.775, -9.28) centre (-49.775, -9.28) ccw
  line L173 (-49.775, -10.28) -> (-64.525, -10.28)
  arc A157 (-65.525, -9.28) -> (-64.525, -10.28) centre (-64.525, -9.28) ccw
  arc A158 (-27.425, 26.82) -> (-28.425, 27.82) centre (-28.425, 26.82) ccw
  line L174 (-28.425, 27.82) -> (-64.525, 27.82)
  arc A159 (-65.525, 28.82) -> (-64.525, 27.82) centre (-64.525, 28.82) ccw
  line L175 (-65.525, 28.82) -> (-65.525, 43.57)
  arc A160 (-64.525, 44.57) -> (-65.525, 43.57) centre (-64.525, 43.57) ccw
  line L176 (-64.525, 44.57) -> (-11.675, 44.57)
  arc A161 (-10.675, 43.57) -> (-11.675, 44.57) centre (-11.675, 43.57) ccw
  line L177 (-10.675, 43.57) -> (-10.675, 23.105)
  arc A162 (-11.675, 22.105) -> (-10.675, 23.105) centre (-11.675, 23.105) ccw
  line L178 (-11.675, 22.105) -> (-26.425, 22.105)
  arc A163 (-27.425, 23.105) -> (-26.425, 22.105) centre (-26.425, 23.105) ccw
  line L179 (-27.425, 23.105) -> (-27.425, 26.82)
  line L180 (-57.8193, 82.0497) -> (-54.0143, 96.3005)
  arc A164 (-52.7901, 97.0086) -> (-54.0143, 96.3005) centre (-53.0481, 96.0425) ccw
  line L181 (-52.7901, 97.0086) -> (-38.5394, 93.2036)
  arc A165 (-37.8312, 91.9795) -> (-38.5394, 93.2036) centre (-38.7973, 92.2375) ccw
  line L182 (-37.8312, 91.9795) -> (-41.6362, 77.7287)
  arc A166 (-42.8603, 77.0206) -> (-41.6362, 77.7287) centre (-42.6023, 77.9867) ccw
  line L183 (-42.8603, 77.0206) -> (-57.1111, 80.8256)
  arc A167 (-57.8193, 82.0497) -> (-57.1111, 80.8256) centre (-56.8531, 81.7917) ccw
  line L184 (19.05, 56) -> (9.525, 56) construction
  line L185 (19.05, 56) -> (19.05, 59.625) construction
  line L186 (9.525, 56) -> (5.9, 56) construction
  line L187 (5.9, 56) -> (5.9, 59.625) construction
  line L188 (0, 46.475) -> (0, 50.1) construction
  line L189 (0, 50.1) -> (5.9, 50.1) construction
  line L190 (5.9, 50.1) -> (5.9, 56) construction
  line L191 (-7.8624, 56.5922) -> (-4.3601, 55.6571) construction
  line L192 (-4.3601, 55.6571) -> (3.0113, 83.265) construction
  line L193 (3.0113, 83.265) -> (3.9495, 86.7664) construction
  line L194 (0, 50.1) -> (-5.8439, 50.1) construction
  line L195 (-5.8439, 50.1) -> (-4.3601, 55.6571) construction
  line L196 (5.9, 59.625) -> (7.05, 59.625) construction
  line L197 (-38.1, 44.57) -> (-38.1, 48.195) construction
  line L198 (-38.1, 48.195) -> (-69.15, 48.195) construction
  line L199 (-38.1, 48.195) -> (-9.525, 48.195) construction
  line L200 (-54.9162, 60.5222) -> (-55.8513, 57.0199) construction
  line L201 (-55.8513, 57.0199) -> (-22.7998, 48.195) construction
  line L202 (-55.8513, 57.0199) -> (-67.4527, 60.1284) construction
  line L203 (7.05, 59.625) -> (5.9, 59.625)
  line L204 (5.9, 59.625) -> (5.9, 50.1)
  line L205 (5.9, 50.1) -> (-5.8439, 50.1)
  line L206 (-5.8439, 50.1) -> (3.6735, 85.6389)
  line L207 (-69.15, 48.195) -> (-22.7998, 48.195)
  line L208 (-67.4527, 60.1284) -> (-22.7998, 48.195)
  dimension "d232" = 9.525
  dimension "d233" = 28.575
  dimension "d234" = 31.05
  dimension "d235" = 28.575
  constraint midpoint L79 L184.start
  constraint parallel L79 L184
  constraint coincident L12 L185.end
  constraint perpendicular L12 L185
  constraint parallel L184 L186
  constraint equal L185 L186
  constraint perpendicular L186 L187
  constraint equal L185 L187
  constraint midpoint L35 L188.start
  constraint perpendicular L35 L188
  constraint perpendicular L188 L189
  constraint collinear L187 L190
  constraint equal L185 L188
  constraint midpoint L103 L191.start
  constraint perpendicular L103 L191
  constraint perpendicular L191 L192
  constraint perpendicular L0 L193
  constraint equal L185 L191
  constraint equal L185 L193
  constraint perpendicular L188 L194
  constraint collinear L192 L195
  constraint coincident L12.end L13.start
  constraint midpoint L176 L197.start
  constraint perpendicular L176 L197
  constraint perpendicular L197 L198
  constraint perpendicular L197 L199
  constraint midpoint L97 L200.start
  constraint perpendicular L97 L200
  constraint equal L185 L197
  constraint equal L185 L200
  constraint coincident L199 L201.end
  constraint perpendicular L200 L201
  constraint coincident L1.end L2.start
  constraint coincident L0.start L13.end
  measures "d232" distance of L184.start L184.end
  measures "d233" distance of L191.end L192.end
  measures "d234" distance of L197.end L2.end
  measures "d235" distance of L197.end L199.end
extrude "Extrude8" add sketch "Sketch4" along normal blind 2.5 contours L13 L203 L204 L205 L206 | L2 L207 L208
fillet "Fillet3" radius 1.5 17 edges at (22.7998, 1.25, 48.195) (67.4527, 1.25, 60.1284) (56.3105, 1.25, 101.7115) (-3.6735, 1.25, 85.6389) (5.8439, 1.25, 50.1) (-5.9, 1.25, 50.1) (-5.9, 1.25, 59.625) (-69.15, 1.25, 59.625) (-69.15, 1.25, -59.625) (-12, 1.25, -59.625) (-12, 1.25, -69.15) (7.05, 1.25, -69.15) (7.05, 1.25, -76.77) (31.05, 1.25, -71.055) (31.05, 1.25, -76.77) (69.15, 1.25, -71.055) (69.15, 1.25, 48.195)
fillet "Fillet4" radius 1 34 edges at (-12.4393, 2.5, -60.0643) (-12, 2.5, -64.3875) (-11.5607, 2.5, -68.7107) (-2.475, 2.5, -69.15) (6.6107, 2.5, -69.5893) (7.05, 2.5, -72.96) (7.4893, 2.5, -76.3307) (19.05, 2.5, -76.77) (30.6107, 2.5, -76.3307) (31.05, 2.5, -73.9125) (31.4893, 2.5, -71.4943) (50.1, 2.5, -71.055) (68.7107, 2.5, -70.6157) (69.15, 2.5, -11.43) (68.7107, 2.5, 47.7557) (50.9362, 2.5, 48.195) (32.7351, 2.5, 49.4997) (49.9188, 2.5, 55.4425) (66.9141, 2.5, 60.4396) (61.8815, 2.5, 80.9205) (55.9999, 2.5, 101.1735) (26.3184, 2.5, 93.6752) (-3.1355, 2.5, 85.3282) (1.0264, 2.5, 68.0891) (5.0793, 2.5, 50.6868) (-0.2553, 2.5, 50.1) (-5.4607, 2.5, 50.5393) (-5.9, 2.5, 54.8625) (-6.3393, 2.5, 59.1857) (-37.525, 2.5, 59.625) (-68.7107, 2.5, 59.1857) (-69.15, 2.5, 0) (-68.7107, 2.5, -59.1857) (-40.575, 2.5, -59.625)
fillet "Fillet5" radius 2.5 12 edges at (63.3816, -2.35, 113.959) (79.15, -2.35, -81.055) (41.05, -0.75, -81.055) (41.05, -0.75, -86.77) (-2.95, -0.75, -86.77) (-2.95, -0.75, -79.15) (-22, -0.75, -79.15) (-22, -0.75, -69.625) (-79.15, -2.35, -69.625) (-79.15, -2.35, 69.625) (-15.8359, -0.75, 69.625) (-12.7285, -0.75, 93.5653)
fillet "Fillet6" radius 105 2 edges at (77.2681, -0.75, 62.1339) (79.15, -0.75, 48.9026)
fillet "Fillet7" radius 0.5 26 edges at (78.2517, 2.5, 54.9922) (79.15, 2.5, -18.634) (78.4178, 2.5, -80.3228) (60.1, 2.5, -81.055) (41.7822, 2.5, -81.7872) (41.05, 2.5, -83.9125) (40.3178, 2.5, -86.0378) (19.05, 2.5, -86.77) (-2.2178, 2.5, -86.0378) (-2.95, 2.5, -82.96) (-3.6822, 2.5, -79.8822) (-12.475, 2.5, -79.15) (-21.2678, 2.5, -78.4178) (-22, 2.5, -74.3875) (-22.7322, 2.5, -70.3572) (-50.575, 2.5, -69.625) (-78.4178, 2.5, -68.8928) (-79.15, 2.5, 0) (-78.4178, 2.5, 68.8928) (-47.3412, 2.5, 69.625) (-16.3823, 2.5, 70.2469) (-14.2486, 2.5, 81.8544) (-12.3459, 2.5, 93.2304) (24.9275, 2.5, 103.6552) (62.8638, 2.5, 113.0622) (69.8004, 2.5, 90.0036)
equation "sw_size_Ref = 19.05 mm"
equation "sw_cut_size_Ref = 14 mm"
equation "sw_cut_space_Ref = sw_size_Ref - sw_cut_size_Ref"
equation "stab_cut_length_Ref = 6 mm"
equation "stab_cut_height_Ref = 12.5 mm"
equation "stabw_length_Ref = 12 mm" comment "Length of the stabilizer wire per unit (e.g. a 2u stabilizer will be stabilizer_wire_length * 2)"
equation "stabw_height_Ref = 2.5 mm"
equation "stabw_cut_length_Ref = 1.7 mm"
equation "stabw_cut_height_Ref = 1 mm"
equation "plt_thickness_Ref = 1.5 mm"
equation "plt_fillet_Ref = 0.25 mm"
equation "pcb_thickness_Ref = 1.6 mm"
equation "m2scr_diameter_Ref = 2.05 mm"
equation "mtscr_head_diameter_Ref = 3.5 mm"
equation "mtscr_head_width_Ref = 0.5 mm"
equation "ctrl_length_Ref = 33 mm"
equation "ctrl_height_Ref = 18 mm"
equation "ctrl_width_Ref = 1.7 mm"
equation "usbc_length_Ref = 8.34 mm"
equation "usbc_height_Ref = 2.56 mm"
equation "bat_length_Ref = 50 mm"
equation "bat_height_Ref = 34 mm"
equation "bat_width_Ref = 5 mm"
equation "bat_clearance_Ref = 3 mm"
equation "key_size_Ref = 16.5 mm"
equation "key_clearance_Ref = 0.25 mm"
equation "key_space_Ref = sw_size_Ref - ( key_size_Ref + key_clearance_Ref )"
equation "key_fillet_Ref = 1 mm"
equation "thrins_diameter_Ref = 3.5 mm"
equation "thrins_depth_Ref = 2.5 mm"
equation "top_inner_thickness_Ref = 1.5 mm"
equation "plt_up_clearance_Ref = 4.9 mm"
equation "alignh_diameter_Ref = 2.5 mm"
equation "alignh_height_Ref = 5 mm"
equation "case_border_width_Ref = 10 mm"
equation "col_mid_offset_Ref = 0.3 * sw_size_Ref"
equation "col_ring_offset_Ref = 0.4 * sw_size_Ref"
equation "col_pinky_offset_Ref = 0.5 * sw_size_Ref"
equation "stab_vert_offset_Ref = 0.6 mm"
equation "stabw_cut_offset_Ref = 0.835 mm"
equation "plt_border_width_Ref = 2.475 mm"
equation "d42 = sw_size_Ref * 7"
equation "d43 = sw_size_Ref * 6"
equation "d44 = 3 * sw_size_Ref"
equation "d45 = col_pinky_offset_Ref"
equation "d46 = sw_size_Ref"
equation "d47 = col_ring_offset_Ref"
equation "d48 = sw_size_Ref"
equation "d49 = col_mid_offset_Ref"
equation "d50 = 2 * sw_size_Ref"
equation "d51 = 3 * sw_size_Ref"
equation "d52 = col_pinky_offset_Ref"
equation "d53 = sw_size_Ref"
equation "d54 = col_ring_offset_Ref - col_mid_offset_Ref"
equation "d55 = plt_border_width_Ref"
equation "d56 = plt_border_width_Ref"
equation "d57 = plt_border_width_Ref"
equation "d58 = plt_border_width_Ref"
equation "d59 = plt_border_width_Ref"
equation "d60 = plt_border_width_Ref"
equation "d61 = plt_border_width_Ref"
equation "d62 = plt_border_width_Ref"
equation "d63 = plt_border_width_Ref"
equation "d64 = plt_border_width_Ref"
equation "d65 = plt_border_width_Ref"
equation "d66 = plt_border_width_Ref"
equation "d67 = plt_border_width_Ref"
equation "d68 = plt_border_width_Ref"
equation "d69 = plt_border_width_Ref"
equation "d70 = plt_border_width_Ref"
equation "d71 = plt_border_width_Ref"
equation "d72 = plt_border_width_Ref"
equation "d73 = plt_border_width_Ref"
equation "d74 = plt_border_width_Ref"
equation "d75 = plt_border_width_Ref"
equation "d76 = plt_border_width_Ref"
equation "d79 = ( sw_size_Ref - 18 mm ) * 0.5"
equation "d80 = ( sw_size_Ref - 18 mm ) * 0.5"
equation "d81 = sw_size_Ref * 3"
equation "d82 = sw_size_Ref * 2"
equation "d83 = plt_border_width_Ref"
equation "d84 = plt_border_width_Ref"
equation "d85 = plt_border_width_Ref"
equation "d86 = plt_border_width_Ref"
equation "d87 = plt_border_width_Ref"
equation "d88 = plt_border_width_Ref"
equation "d89 = -case_border_width_Ref"
equation "d90 = -top_inner_thickness_Ref"
equation "d92 = -case_top_thickness_Ref"
equation "case_top_thickness_Ref = 4 mm"
equation "d95 = case_border_width_Ref + plt_border_width_Ref"
equation "d96 = plt_border_width_Ref + case_border_width_Ref"
equation "d97 = sw_size_Ref"
equation "d98 = sw_size_Ref * 2"
equation "d99 = col_pinky_offset_Ref"
equation "d100 = sw_size_Ref"
equation "d101 = col_ring_offset_Ref"
equation "d102 = sw_size_Ref"
equation "d103 = col_mid_offset_Ref"
equation "d104 = sw_size_Ref"
equation "d105 = sw_size_Ref"
equation "d106 = sw_size_Ref * 5"
equation "d107 = sw_size_Ref * 2"
equation "d108 = sw_size_Ref"
equation "d109 = sw_size_Ref - col_ring_offset_Ref"
equation "d110 = sw_size_Ref - col_pinky_offset_Ref"
equation "d111 = sw_size_Ref"
equation "d112 = 4 * sw_size_Ref"
equation "d113 = 5 * sw_size_Ref"
equation "d114 = sw_size_Ref"
equation "d115 = sw_size_Ref"
equation "d116 = sw_size_Ref"
equation "d117 = sw_size_Ref * 3"
equation "d118 = sw_size_Ref"
equation "d119 = sw_size_Ref"
equation "d120 = sw_size_Ref * 2"
equation "d121 = sw_size_Ref"
equation "d122 = sw_size_Ref"
equation "d123 = sw_size_Ref"
equation "d124 = sw_size_Ref"
equation "d125 = sw_size_Ref"
equation "d128 = ( sw_size_Ref - 18 mm ) * 0.5"
equation "d129 = ( sw_size_Ref - 18 mm ) * 0.5"
equation "d130 = sw_size_Ref"
equation "d131 = sw_size_Ref"
equation "d132 = sw_size_Ref"
equation "d133 = sw_size_Ref"
equation "d134 = sw_size_Ref * 3"
equation "d135 = sw_size_Ref * 2"
equation "d136 = key_size_Ref + key_clearance_Ref"
equation "d137 = key_size_Ref + key_clearance_Ref"
equation "d140 = -sw_size_Ref"
equation "d141 = sw_size_Ref"
equation "d142 = key_size_Ref + key_clearance_Ref"
equation "d143 = key_size_Ref + key_clearance_Ref"
equation "d144 = key_size_Ref + key_clearance_Ref"
equation "d145 = key_size_Ref + key_clearance_Ref"
equation "d146 = key_size_Ref + key_clearance_Ref"
equation "d147 = key_size_Ref + key_clearance_Ref"
equation "d148 = key_size_Ref + key_clearance_Ref"
equation "d149 = key_size_Ref + key_clearance_Ref"
equation "d150 = key_size_Ref + key_clearance_Ref"
equation "d151 = key_size_Ref + key_clearance_Ref"
equation "d152 = key_size_Ref + key_clearance_Ref + sw_size_Ref"
equation "d153 = key_size_Ref + key_clearance_Ref"
equation "d154 = key_size_Ref + key_clearance_Ref + sw_size_Ref * 2"
equation "d155 = key_size_Ref + key_clearance_Ref"
equation "d156 = key_size_Ref + key_clearance_Ref"
equation "d157 = col_mid_offset_Ref"
equation "d160 = -sw_size_Ref"
equation "d164 = -sw_size_Ref"
equation "d166 = key_size_Ref + key_clearance_Ref"
equation "d167 = key_size_Ref + key_clearance_Ref"
equation "d171 = sw_size_Ref"
equation "d175 = sw_size_Ref"
equation "d179 = sw_size_Ref"
equation "d182 = -sw_size_Ref"
equation "d183 = sw_size_Ref"
equation "d187 = sw_size_Ref * 2"
equation "d191 = sw_size_Ref"
equation "d194 = key_fillet_Ref"
equation "d195 = top_align_mark_length_Ref"
equation "d196 = top_align_mark_length_Ref"
equation "d197 = top_align_mark_length_Ref"
equation "d198 = top_align_mark_length_Ref"
equation "d199 = top_align_mark_length_Ref"
equation "d200 = top_align_mark_length_Ref"
equation "d201 = top_align_mark_length_Ref"
equation "d202 = top_align_mark_length_Ref"
equation "d203 = case_border_width_Ref * 1.75"
equation "d204 = thrins_diameter_Ref"
equation "d205 = case_border_width_Ref * 1.75"
equation "d206 = case_border_width_Ref * 1.75"
equation "d207 = case_border_width_Ref * 1.75"
equation "d208 = thrins_diameter_Ref"
equation "d209 = thrins_diameter_Ref"
equation "d210 = thrins_diameter_Ref"
equation "d211 = plt_up_clearance_Ref - case_top_thickness_Ref + plt_thickness_Ref + pcb_thickness_Ref * 0.5 - thrins_depth_Ref"
equation "d213 = plt_up_clearance_Ref - case_top_thickness_Ref + plt_thickness_Ref + pcb_thickness_Ref * 0.5"
equation "top_align_mark_length_Ref = 10 mm"